Autodesk Fusion 360 part; units mm, degrees
(part 3 of 3)
  line L378 (13, -21.2) -> (9, -21.2)
  line L379 (9, -21.2) -> (9, -21.8)
  line L380 (10.7, -23.5) -> (11.3, -23.5)
  line L381 (11.3, -23.5) -> (11.3, -19.5)
  line L382 (11.3, -19.5) -> (10.7, -19.5)
  line L383 (10.7, -19.5) -> (10.7, -23.5)
  line L384 (-13, -11.3) -> (-9, -11.3)
  line L385 (-9, -11.3) -> (-9, -10.7)
  line L386 (-9, -10.7) -> (-13, -10.7)
  line L387 (-13, -10.7) -> (-13, -11.3)
  line L388 (-11.3, -13) -> (-10.7, -13)
  line L389 (-10.7, -13) -> (-10.7, -9)
  line L390 (-10.7, -9) -> (-11.3, -9)
  line L391 (-11.3, -9) -> (-11.3, -13)
  line L392 (-13, 10.7) -> (-9, 10.7)
  line L393 (-9, 10.7) -> (-9, 11.3)
  line L394 (-9, 11.3) -> (-13, 11.3)
  line L395 (-13, 11.3) -> (-13, 10.7)
  line L396 (-11.3, 9) -> (-10.7, 9)
  line L397 (-10.7, 9) -> (-10.7, 13)
  line L398 (-10.7, 13) -> (-11.3, 13)
  line L399 (-11.3, 13) -> (-11.3, 9)
  line L400 (9, -11.3) -> (13, -11.3)
  line L401 (13, -11.3) -> (13, -10.7)
  line L402 (13, -10.7) -> (9, -10.7)
  line L403 (9, -10.7) -> (9, -11.3)
  line L404 (10.7, -13) -> (11.3, -13)
  line L405 (11.3, -13) -> (11.3, -9)
  line L406 (11.3, -9) -> (10.7, -9)
  line L407 (10.7, -9) -> (10.7, -13)
  line L408 (9, 10.7) -> (13, 10.7)
  line L409 (13, 10.7) -> (13, 11.3)
  line L410 (13, 11.3) -> (9, 11.3)
  line L411 (9, 11.3) -> (9, 10.7)
  line L412 (10.7, 9) -> (11.3, 9)
  line L413 (11.3, 9) -> (11.3, 13)
  line L414 (11.3, 13) -> (10.7, 13)
  line L415 (10.7, 13) -> (10.7, 9)
  line L416 (-13, 21.2) -> (-9, 21.2)
  line L417 (-9, 21.2) -> (-9, 21.8)
  line L418 (-9, 21.8) -> (-13, 21.8)
  line L419 (-13, 21.8) -> (-13, 21.2)
  line L420 (-11.3, 19.5) -> (-10.7, 19.5)
  line L421 (-10.7, 19.5) -> (-10.7, 23.5)
  line L422 (-10.7, 23.5) -> (-11.3, 23.5)
  line L423 (-11.3, 23.5) -> (-11.3, 19.5)
  line L424 (-13, 43.2) -> (-9, 43.2)
  line L425 (-9, 43.2) -> (-9, 43.8)
  line L426 (-9, 43.8) -> (-13, 43.8)
  line L427 (-13, 43.8) -> (-13, 43.2)
  line L428 (-11.3, 41.5) -> (-10.7, 41.5)
  line L429 (-10.7, 41.5) -> (-10.7, 45.5)
  line L430 (-10.7, 45.5) -> (-11.3, 45.5)
  line L431 (-11.3, 45.5) -> (-11.3, 41.5)
  line L432 (9, 21.2) -> (13, 21.2)
  line L433 (13, 21.2) -> (13, 21.8)
  line L434 (13, 21.8) -> (9, 21.8)
  line L435 (9, 21.8) -> (9, 21.2)
  line L436 (10.7, 19.5) -> (11.3, 19.5)
  line L437 (11.3, 19.5) -> (11.3, 23.5)
  line L438 (11.3, 23.5) -> (10.7, 23.5)
  line L439 (10.7, 23.5) -> (10.7, 19.5)
  line L440 (9, 43.2) -> (13, 43.2)
  line L441 (13, 43.2) -> (13, 43.8)
  line L442 (13, 43.8) -> (9, 43.8)
  line L443 (9, 43.8) -> (9, 43.2)
  line L444 (10.7, 41.5) -> (11.3, 41.5)
  line L445 (11.3, 41.5) -> (11.3, 45.5)
  line L446 (11.3, 45.5) -> (10.7, 45.5)
  line L447 (10.7, 45.5) -> (10.7, 41.5)
  line L448 (-13, 53.7) -> (-9, 53.7)
  line L449 (-9, 53.7) -> (-9, 54.3)
  line L450 (-9, 54.3) -> (-13, 54.3)
  line L451 (-13, 54.3) -> (-13, 53.7)
  line L452 (-11.3, 52) -> (-10.7, 52)
  line L453 (-10.7, 52) -> (-10.7, 56)
  line L454 (-10.7, 56) -> (-11.3, 56)
  line L455 (-11.3, 56) -> (-11.3, 52)
  line L456 (-13, 75.7) -> (-9, 75.7)
  line L457 (-9, 75.7) -> (-9, 76.3)
  line L458 (-9, 76.3) -> (-13, 76.3)
  line L459 (-13, 76.3) -> (-13, 75.7)
  line L460 (-11.3, 74) -> (-10.7, 74)
  line L461 (-10.7, 74) -> (-10.7, 78)
  line L462 (-10.7, 78) -> (-11.3, 78)
  line L463 (-11.3, 78) -> (-11.3, 74)
  line L464 (9, 53.7) -> (13, 53.7)
  line L465 (13, 53.7) -> (13, 54.3)
  line L466 (13, 54.3) -> (9, 54.3)
  line L467 (9, 54.3) -> (9, 53.7)
  line L468 (10.7, 52) -> (11.3, 52)
  line L469 (11.3, 52) -> (11.3, 56)
  line L470 (11.3, 56) -> (10.7, 56)
  line L471 (10.7, 56) -> (10.7, 52)
  line L472 (9, 75.7) -> (13, 75.7)
  line L473 (13, 75.7) -> (13, 76.3)
  line L474 (13, 76.3) -> (9, 76.3)
  line L475 (9, 76.3) -> (9, 75.7)
  line L476 (10.7, 74) -> (11.3, 74)
  line L477 (11.3, 74) -> (11.3, 78)
  line L478 (11.3, 78) -> (10.7, 78)
  line L479 (10.7, 78) -> (10.7, 74)
  line L480 (19.5, -76.3) -> (23.5, -76.3)
  line L481 (23.5, -76.3) -> (23.5, -75.7)
  line L482 (23.5, -75.7) -> (19.5, -75.7)
  line L483 (19.5, -75.7) -> (19.5, -76.3)
  line L484 (21.2, -78) -> (21.8, -78)
  line L485 (21.8, -78) -> (21.8, -74)
  line L486 (21.8, -74) -> (21.2, -74)
  line L487 (21.2, -74) -> (21.2, -78)
  line L488 (19.5, -54.3) -> (23.5, -54.3)
  line L489 (23.5, -54.3) -> (23.5, -53.7)
  line L490 (23.5, -53.7) -> (19.5, -53.7)
  line L491 (19.5, -53.7) -> (19.5, -54.3)
  line L492 (21.2, -56) -> (21.8, -56)
  line L493 (21.8, -56) -> (21.8, -52)
  line L494 (21.8, -52) -> (21.2, -52)
  line L495 (21.2, -52) -> (21.2, -56)
  line L496 (41.5, -76.3) -> (45.5, -76.3)
  line L497 (45.5, -76.3) -> (45.5, -75.7)
  line L498 (45.5, -75.7) -> (41.5, -75.7)
  line L499 (41.5, -75.7) -> (41.5, -76.3)
  line L500 (43.2, -78) -> (43.8, -78)
  line L501 (43.8, -78) -> (43.8, -74)
  line L502 (43.8, -74) -> (43.2, -74)
  line L503 (43.2, -74) -> (43.2, -78)
  line L504 (41.5, -54.3) -> (45.5, -54.3)
  line L505 (45.5, -54.3) -> (45.5, -53.7)
  line L506 (45.5, -53.7) -> (41.5, -53.7)
  line L507 (41.5, -53.7) -> (41.5, -54.3)
  line L508 (43.2, -56) -> (43.8, -56)
  line L509 (43.8, -56) -> (43.8, -52)
  line L510 (43.8, -52) -> (43.2, -52)
  line L511 (43.2, -52) -> (43.2, -56)
  line L512 (19.5, -43.8) -> (23.5, -43.8)
  line L513 (23.5, -43.8) -> (23.5, -43.2)
  line L514 (23.5, -43.2) -> (19.5, -43.2)
  line L515 (19.5, -43.2) -> (19.5, -43.8)
  line L516 (21.2, -45.5) -> (21.8, -45.5)
  line L517 (21.8, -45.5) -> (21.8, -41.5)
  line L518 (21.8, -41.5) -> (21.2, -41.5)
  line L519 (21.2, -41.5) -> (21.2, -45.5)
  line L520 (19.5, -21.8) -> (23.5, -21.8)
  line L521 (23.5, -21.8) -> (23.5, -21.2)
  line L522 (23.5, -21.2) -> (19.5, -21.2)
  line L523 (19.5, -21.2) -> (19.5, -21.8)
  line L524 (21.2, -23.5) -> (21.8, -23.5)
  line L525 (21.8, -23.5) -> (21.8, -19.5)
  line L526 (21.8, -19.5) -> (21.2, -19.5)
  line L527 (21.2, -19.5) -> (21.2, -23.5)
  line L528 (41.5, -43.8) -> (45.5, -43.8)
  line L529 (45.5, -43.8) -> (45.5, -43.2)
  line L530 (45.5, -43.2) -> (41.5, -43.2)
  line L531 (41.5, -43.2) -> (41.5, -43.8)
  line L532 (43.2, -45.5) -> (43.8, -45.5)
  line L533 (43.8, -45.5) -> (43.8, -41.5)
  line L534 (43.8, -41.5) -> (43.2, -41.5)
  line L535 (43.2, -41.5) -> (43.2, -45.5)
  line L536 (41.5, -21.8) -> (45.5, -21.8)
  line L537 (45.5, -21.8) -> (45.5, -21.2)
  line L538 (45.5, -21.2) -> (41.5, -21.2)
  line L539 (41.5, -21.2) -> (41.5, -21.8)
  line L540 (43.2, -23.5) -> (43.8, -23.5)
  line L541 (43.8, -23.5) -> (43.8, -19.5)
  line L542 (43.8, -19.5) -> (43.2, -19.5)
  line L543 (43.2, -19.5) -> (43.2, -23.5)
  line L544 (19.5, -11.3) -> (23.5, -11.3)
  line L545 (23.5, -11.3) -> (23.5, -10.7)
  line L546 (23.5, -10.7) -> (19.5, -10.7)
  line L547 (19.5, -10.7) -> (19.5, -11.3)
  line L548 (21.2, -13) -> (21.8, -13)
  line L549 (21.8, -13) -> (21.8, -9)
  line L550 (21.8, -9) -> (21.2, -9)
  line L551 (21.2, -9) -> (21.2, -13)
  line L552 (19.5, 10.7) -> (23.5, 10.7)
  line L553 (23.5, 10.7) -> (23.5, 11.3)
  line L554 (23.5, 11.3) -> (19.5, 11.3)
  line L555 (19.5, 11.3) -> (19.5, 10.7)
  line L556 (21.2, 9) -> (21.8, 9)
  line L557 (21.8, 9) -> (21.8, 13)
  line L558 (21.8, 13) -> (21.2, 13)
  line L559 (21.2, 13) -> (21.2, 9)
  line L560 (41.5, -11.3) -> (45.5, -11.3)
  line L561 (45.5, -11.3) -> (45.5, -10.7)
  line L562 (45.5, -10.7) -> (41.5, -10.7)
  line L563 (41.5, -10.7) -> (41.5, -11.3)
  line L564 (43.2, -13) -> (43.8, -13)
  line L565 (43.8, -13) -> (43.8, -9)
  line L566 (43.8, -9) -> (43.2, -9)
  line L567 (43.2, -9) -> (43.2, -13)
  line L568 (41.5, 10.7) -> (45.5, 10.7)
  line L569 (45.5, 10.7) -> (45.5, 11.3)
  line L570 (45.5, 11.3) -> (41.5, 11.3)
  line L571 (41.5, 11.3) -> (41.5, 10.7)
  line L572 (43.2, 9) -> (43.8, 9)
  line L573 (43.8, 9) -> (43.8, 13)
  line L574 (43.8, 13) -> (43.2, 13)
  line L575 (43.2, 13) -> (43.2, 9)
  line L576 (19.5, 21.2) -> (23.5, 21.2)
  line L577 (23.5, 21.2) -> (23.5, 21.8)
  line L578 (23.5, 21.8) -> (19.5, 21.8)
  line L579 (19.5, 21.8) -> (19.5, 21.2)
  line L580 (21.2, 19.5) -> (21.8, 19.5)
  line L581 (21.8, 19.5) -> (21.8, 23.5)
  line L582 (21.8, 23.5) -> (21.2, 23.5)
  line L583 (21.2, 23.5) -> (21.2, 19.5)
  line L584 (19.5, 43.2) -> (23.5, 43.2)
  line L585 (23.5, 43.2) -> (23.5, 43.8)
  line L586 (23.5, 43.8) -> (19.5, 43.8)
  line L587 (19.5, 43.8) -> (19.5, 43.2)
  line L588 (21.2, 41.5) -> (21.8, 41.5)
  line L589 (21.8, 41.5) -> (21.8, 45.5)
  line L590 (21.8, 45.5) -> (21.2, 45.5)
  line L591 (21.2, 45.5) -> (21.2, 41.5)
  line L592 (41.5, 21.2) -> (45.5, 21.2)
  line L593 (45.5, 21.2) -> (45.5, 21.8)
  line L594 (45.5, 21.8) -> (41.5, 21.8)
  line L595 (41.5, 21.8) -> (41.5, 21.2)
  line L596 (43.2, 19.5) -> (43.8, 19.5)
  line L597 (43.8, 19.5) -> (43.8, 23.5)
  line L598 (43.8, 23.5) -> (43.2, 23.5)
  line L599 (43.2, 23.5) -> (43.2, 19.5)
  line L600 (41.5, 43.2) -> (45.5, 43.2)
  line L601 (45.5, 43.2) -> (45.5, 43.8)
  line L602 (45.5, 43.8) -> (41.5, 43.8)
  line L603 (41.5, 43.8) -> (41.5, 43.2)
  line L604 (43.2, 41.5) -> (43.8, 41.5)
  line L605 (43.8, 41.5) -> (43.8, 45.5)
  line L606 (43.8, 45.5) -> (43.2, 45.5)
  line L607 (43.2, 45.5) -> (43.2, 41.5)
  line L608 (19.5, 53.7) -> (23.5, 53.7)
  line L609 (23.5, 53.7) -> (23.5, 54.3)
  line L610 (23.5, 54.3) -> (19.5, 54.3)
  line L611 (19.5, 54.3) -> (19.5, 53.7)
  line L612 (21.2, 52) -> (21.8, 52)
  line L613 (21.8, 52) -> (21.8, 56)
  line L614 (21.8, 56) -> (21.2, 56)
  line L615 (21.2, 56) -> (21.2, 52)
  line L616 (19.5, 75.7) -> (23.5, 75.7)
  line L617 (23.5, 75.7) -> (23.5, 76.3)
  line L618 (23.5, 76.3) -> (19.5, 76.3)
  line L619 (19.5, 76.3) -> (19.5, 75.7)
  line L620 (21.2, 74) -> (21.8, 74)
  line L621 (21.8, 74) -> (21.8, 78)
  line L622 (21.8, 78) -> (21.2, 78)
  line L623 (21.2, 78) -> (21.2, 74)
  line L624 (41.5, 53.7) -> (45.5, 53.7)
  line L625 (45.5, 53.7) -> (45.5, 54.3)
  line L626 (45.5, 54.3) -> (41.5, 54.3)
  line L627 (41.5, 54.3) -> (41.5, 53.7)
  line L628 (43.2, 52) -> (43.8, 52)
  line L629 (43.8, 52) -> (43.8, 56)
  line L630 (43.8, 56) -> (43.2, 56)
  line L631 (43.2, 56) -> (43.2, 52)
  line L632 (41.5, 75.7) -> (45.5, 75.7)
  line L633 (45.5, 75.7) -> (45.5, 76.3)
  line L634 (45.5, 76.3) -> (41.5, 76.3)
  line L635 (41.5, 76.3) -> (41.5, 75.7)
  line L636 (43.2, 74) -> (43.8, 74)
  line L637 (43.8, 74) -> (43.8, 78)
  line L638 (43.8, 78) -> (43.2, 78)
  line L639 (43.2, 78) -> (43.2, 74)
  line L640 (52, -76.3) -> (56, -76.3)
  line L641 (56, -76.3) -> (56, -75.7)
  line L642 (56, -75.7) -> (52, -75.7)
  line L643 (52, -75.7) -> (52, -76.3)
  line L644 (53.7, -78) -> (54.3, -78)
  line L645 (54.3, -78) -> (54.3, -74)
  line L646 (54.3, -74) -> (53.7, -74)
  line L647 (53.7, -74) -> (53.7, -78)
  line L648 (52, -54.3) -> (56, -54.3)
  line L649 (56, -54.3) -> (56, -53.7)
  line L650 (56, -53.7) -> (52, -53.7)
  line L651 (52, -53.7) -> (52, -54.3)
  line L652 (53.7, -56) -> (54.3, -56)
  line L653 (54.3, -56) -> (54.3, -52)
  line L654 (54.3, -52) -> (53.7, -52)
  line L655 (53.7, -52) -> (53.7, -56)
  line L656 (74, -76.3) -> (78, -76.3)
  line L657 (78, -76.3) -> (78, -75.7)
  line L658 (78, -75.7) -> (74, -75.7)
  line L659 (74, -75.7) -> (74, -76.3)
  line L660 (75.7, -78) -> (76.3, -78)
  line L661 (76.3, -78) -> (76.3, -74)
  line L662 (76.3, -74) -> (75.7, -74)
  line L663 (75.7, -74) -> (75.7, -78)
  line L664 (74, -54.3) -> (78, -54.3)
  line L665 (78, -54.3) -> (78, -53.7)
  line L666 (78, -53.7) -> (74, -53.7)
  line L667 (74, -53.7) -> (74, -54.3)
  line L668 (75.7, -56) -> (76.3, -56)
  line L669 (76.3, -56) -> (76.3, -52)
  line L670 (76.3, -52) -> (75.7, -52)
  line L671 (75.7, -52) -> (75.7, -56)
  line L672 (52, -43.8) -> (56, -43.8)
  line L673 (56, -43.8) -> (56, -43.2)
  line L674 (56, -43.2) -> (52, -43.2)
  line L675 (52, -43.2) -> (52, -43.8)
  line L676 (53.7, -45.5) -> (54.3, -45.5)
  line L677 (54.3, -45.5) -> (54.3, -41.5)
  line L678 (54.3, -41.5) -> (53.7, -41.5)
  line L679 (53.7, -41.5) -> (53.7, -45.5)
  line L680 (52, -21.8) -> (56, -21.8)
  line L681 (56, -21.8) -> (56, -21.2)
  line L682 (56, -21.2) -> (52, -21.2)
  line L683 (52, -21.2) -> (52, -21.8)
  line L684 (53.7, -23.5) -> (54.3, -23.5)
  line L685 (54.3, -23.5) -> (54.3, -19.5)
  line L686 (54.3, -19.5) -> (53.7, -19.5)
  line L687 (53.7, -19.5) -> (53.7, -23.5)
  line L688 (74, -43.8) -> (78, -43.8)
  line L689 (78, -43.8) -> (78, -43.2)
  line L690 (78, -43.2) -> (74, -43.2)
  line L691 (74, -43.2) -> (74, -43.8)
  line L692 (75.7, -45.5) -> (76.3, -45.5)
  line L693 (76.3, -45.5) -> (76.3, -41.5)
  line L694 (76.3, -41.5) -> (75.7, -41.5)
  line L695 (75.7, -41.5) -> (75.7, -45.5)
  line L696 (74, -21.8) -> (78, -21.8)
  line L697 (78, -21.8) -> (78, -21.2)
  line L698 (78, -21.2) -> (74, -21.2)
  line L699 (74, -21.2) -> (74, -21.8)
  line L700 (75.7, -23.5) -> (76.3, -23.5)
  line L701 (76.3, -23.5) -> (76.3, -19.5)
  line L702 (76.3, -19.5) -> (75.7, -19.5)
  line L703 (75.7, -19.5) -> (75.7, -23.5)
  line L704 (52, -11.3) -> (56, -11.3)
  line L705 (56, -11.3) -> (56, -10.7)
  line L706 (56, -10.7) -> (52, -10.7)
  line L707 (52, -10.7) -> (52, -11.3)
  line L708 (53.7, -13) -> (54.3, -13)
  line L709 (54.3, -13) -> (54.3, -9)
  line L710 (54.3, -9) -> (53.7, -9)
  line L711 (53.7, -9) -> (53.7, -13)
  line L712 (52, 10.7) -> (56, 10.7)
  line L713 (56, 10.7) -> (56, 11.3)
  line L714 (56, 11.3) -> (52, 11.3)
  line L715 (52, 11.3) -> (52, 10.7)
  line L716 (53.7, 9) -> (54.3, 9)
  line L717 (54.3, 9) -> (54.3, 13)
  line L718 (54.3, 13) -> (53.7, 13)
  line L719 (53.7, 13) -> (53.7, 9)
  line L720 (74, -11.3) -> (78, -11.3)
  line L721 (78, -11.3) -> (78, -10.7)
  line L722 (78, -10.7) -> (74, -10.7)
  line L723 (74, -10.7) -> (74, -11.3)
  line L724 (75.7, -13) -> (76.3, -13)
  line L725 (76.3, -13) -> (76.3, -9)
  line L726 (76.3, -9) -> (75.7, -9)
  line L727 (75.7, -9) -> (75.7, -13)
  line L728 (74, 10.7) -> (78, 10.7)
  line L729 (78, 10.7) -> (78, 11.3)
  line L730 (78, 11.3) -> (74, 11.3)
  line L731 (74, 11.3) -> (74, 10.7)
  line L732 (75.7, 9) -> (76.3, 9)
  line L733 (76.3, 9) -> (76.3, 13)
  line L734 (76.3, 13) -> (75.7, 13)
  line L735 (75.7, 13) -> (75.7, 9)
  line L736 (52, 21.2) -> (56, 21.2)
  line L737 (56, 21.2) -> (56, 21.8)
  line L738 (56, 21.8) -> (52, 21.8)
  line L739 (52, 21.8) -> (52, 21.2)
  line L740 (53.7, 19.5) -> (54.3, 19.5)
  line L741 (54.3, 19.5) -> (54.3, 23.5)
  line L742 (54.3, 23.5) -> (53.7, 23.5)
  line L743 (53.7, 23.5) -> (53.7, 19.5)
  line L744 (52, 43.2) -> (56, 43.2)
  line L745 (56, 43.2) -> (56, 43.8)
  line L746 (56, 43.8) -> (52, 43.8)
  line L747 (52, 43.8) -> (52, 43.2)
  line L748 (53.7, 41.5) -> (54.3, 41.5)
  line L749 (54.3, 41.5) -> (54.3, 45.5)
  line L750 (54.3, 45.5) -> (53.7, 45.5)
  line L751 (53.7, 45.5) -> (53.7, 41.5)
  line L752 (74, 21.2) -> (78, 21.2)
  line L753 (78, 21.2) -> (78, 21.8)
  line L754 (78, 21.8) -> (74, 21.8)
  line L755 (74, 21.8) -> (74, 21.2)
  line L756 (75.7, 19.5) -> (76.3, 19.5)
  line L757 (76.3, 19.5) -> (76.3, 23.5)
  line L758 (76.3, 23.5) -> (75.7, 23.5)
  line L759 (75.7, 23.5) -> (75.7, 19.5)
  line L760 (74, 43.2) -> (78, 43.2)
  line L761 (78, 43.2) -> (78, 43.8)
  line L762 (78, 43.8) -> (74, 43.8)
  line L763 (74, 43.8) -> (74, 43.2)
  line L764 (75.7, 41.5) -> (76.3, 41.5)
  line L765 (76.3, 41.5) -> (76.3, 45.5)
  line L766 (76.3, 45.5) -> (75.7, 45.5)
  line L767 (75.7, 45.5) -> (75.7, 41.5)
  line L768 (52, 53.7) -> (56, 53.7)
  line L769 (56, 53.7) -> (56, 54.3)
  line L770 (56, 54.3) -> (52, 54.3)
  line L771 (52, 54.3) -> (52, 53.7)
  line L772 (53.7, 52) -> (54.3, 52)
  line L773 (54.3, 52) -> (54.3, 56)
  line L774 (54.3, 56) -> (53.7, 56)
  line L775 (53.7, 56) -> (53.7, 52)
  line L776 (52, 75.7) -> (56, 75.7)
  line L777 (56, 75.7) -> (56, 76.3)
  line L778 (56, 76.3) -> (52, 76.3)
  line L779 (52, 76.3) -> (52, 75.7)
  line L780 (53.7, 74) -> (54.3, 74)
  line L781 (54.3, 74) -> (54.3, 78)
  line L782 (54.3, 78) -> (53.7, 78)
  line L783 (53.7, 78) -> (53.7, 74)
  line L784 (74, 53.7) -> (78, 53.7)
  line L785 (78, 53.7) -> (78, 54.3)
  line L786 (78, 54.3) -> (74, 54.3)
  line L787 (74, 54.3) -> (74, 53.7)
  line L788 (75.7, 52) -> (76.3, 52)
  line L789 (76.3, 52) -> (76.3, 56)
  line L790 (76.3, 56) -> (75.7, 56)
  line L791 (75.7, 56) -> (75.7, 52)
  line L792 (74, 75.7) -> (78, 75.7)
  line L793 (78, 75.7) -> (78, 76.3)
  line L794 (78, 76.3) -> (74, 76.3)
  line L795 (74, 76.3) -> (74, 75.7)
  line L796 (75.7, 74) -> (76.3, 74)
  line L797 (76.3, 74) -> (76.3, 78)
  line L798 (76.3, 78) -> (75.7, 78)
  line L799 (75.7, 78) -> (75.7, 74)
extrude "scale_crosses (1)" cut sketch "scale_crosses" against normal blind 0.4 bodies 1 in component "drop_plate"
ref_plane "WorkPlane1" through (0, 0, 0) normal (0, 0, 1) x (1, 0, 0) in component "atoms3_mock"
sketch "outer" plane through (0, 0, 0) normal (0, 0, 1) x (1, 0, 0) in component "atoms3_mock"
  line L0 (-9, -12) -> (9, -12)
  line L1 (12, -9) -> (12, 9)
  line L2 (9, 12) -> (-9, 12)
  line L3 (-12, 9) -> (-12, -9)
  arc A0 (9, -12) -> (12, -9) centre (9, -9) ccw
  arc A1 (12, 9) -> (9, 12) centre (9, 9) ccw
  arc A2 (-9, 12) -> (-12, 9) centre (-9, 9) ccw
  arc A3 (-12, -9) -> (-9, -12) centre (-9, -9) ccw
  constraint tangent L0 A0
  constraint tangent L1 A0
  constraint tangent L1 A1
  constraint tangent L2 A1
  constraint tangent L2 A2
  constraint tangent L3 A2
  constraint tangent L3 A3
  constraint tangent L0 A3
extrude "outer (1)" add sketch "outer" along normal blind 12.9 separate body makes body 2 in component "atoms3_mock"
ref_plane "WorkPlane2" through (0, 0, 0) normal (0, 0, 1) x (1, 0, 0) in component "atoms3_mock"
sketch "cavity" plane through (0, 0, 0) normal (0, 0, 1) x (1, 0, 0) in component "atoms3_mock"
  line L0 (-9, -10.4) -> (9, -10.4)
  line L1 (10.4, -9) -> (10.4, 9)
  line L2 (9, 10.4) -> (-9, 10.4)
  line L3 (-10.4, 9) -> (-10.4, -9)
  arc A0 (9, -10.4) -> (10.4, -9) centre (9, -9) ccw
  arc A1 (10.4, 9) -> (9, 10.4) centre (9, 9) ccw
  arc A2 (-9, 10.4) -> (-10.4, 9) centre (-9, 9) ccw
  arc A3 (-10.4, -9) -> (-9, -10.4) centre (-9, -9) ccw
  constraint tangent L0 A0
  constraint tangent L1 A0
  constraint tangent L1 A1
  constraint tangent L2 A1
  constraint tangent L2 A2
  constraint tangent L3 A2
  constraint tangent L3 A3
  constraint tangent L0 A3
extrude "cavity (1)" cut sketch "cavity" along normal blind 9.9 bodies 2 in component "atoms3_mock"
ref_plane "WorkPlane3" through (0, 0, 12.9) normal (0, 0, 1) x (1, 0, 0) in component "atoms3_mock"
sketch "window_chamfer" plane through (0, 0, 12.9) normal (0, 0, 1) x (1, 0, 0) in component "atoms3_mock"
  line L0 (-7.7, -8.9) -> (7.7, -8.9)
  line L1 (8.9, -7.7) -> (8.9, 7.7)
  line L2 (7.7, 8.9) -> (-7.7, 8.9)
  line L3 (-8.9, 7.7) -> (-8.9, -7.7)
  arc A0 (7.7, -8.9) -> (8.9, -7.7) centre (7.7, -7.7) ccw
  arc A1 (8.9, 7.7) -> (7.7, 8.9) centre (7.7, 7.7) ccw
  arc A2 (-7.7, 8.9) -> (-8.9, 7.7) centre (-7.7, 7.7) ccw
  arc A3 (-8.9, -7.7) -> (-7.7, -8.9) centre (-7.7, -7.7) ccw
  constraint tangent L0 A0
  constraint tangent L1 A0
  constraint tangent L1 A1
  constraint tangent L2 A1
  constraint tangent L2 A2
  constraint tangent L3 A2
  constraint tangent L3 A3
  constraint tangent L0 A3
extrude "window_chamfer (1)" cut sketch "window_chamfer" against normal blind 0.8 draft -45 bodies 2 in component "atoms3_mock"
ref_plane "WorkPlane4" through (0, 0, 12.9) normal (0, 0, 1) x (1, 0, 0) in component "atoms3_mock"
sketch "screen_recess" plane through (0, 0, 12.9) normal (0, 0, 1) x (1, 0, 0) in component "atoms3_mock"
  line L0 (-7.7, -8.1) -> (7.7, -8.1)
  line L1 (8.1, -7.7) -> (8.1, 7.7)
  line L2 (7.7, 8.1) -> (-7.7, 8.1)
  line L3 (-8.1, 7.7) -> (-8.1, -7.7)
  arc A0 (7.7, -8.1) -> (8.1, -7.7) centre (7.7, -7.7) ccw
  arc A1 (8.1, 7.7) -> (7.7, 8.1) centre (7.7, 7.7) ccw
  arc A2 (-7.7, 8.1) -> (-8.1, 7.7) centre (-7.7, 7.7) ccw
  arc A3 (-8.1, -7.7) -> (-7.7, -8.1) centre (-7.7, -7.7) ccw
  constraint tangent L0 A0
  constraint tangent L1 A0
  constraint tangent L1 A1
  constraint tangent L2 A1
  constraint tangent L2 A2
  constraint tangent L3 A2
  constraint tangent L3 A3
  constraint tangent L0 A3
extrude "screen_recess (1)" cut sketch "screen_recess" against normal blind 1.2 bodies 2 in component "atoms3_mock"
ref_plane "WorkPlane5" through (0, 0, 11.7) normal (0, 0, 1) x (1, 0, 0) in component "atoms3_mock"
sketch "screen_mark" plane through (0, 0, 11.7) normal (0, 0, 1) x (1, 0, 0) in component "atoms3_mock"
  line L0 (-7, -7.8) -> (7, -7.8)
  line L1 (7.8, -7) -> (7.8, 7)
  line L2 (7, 7.8) -> (-7, 7.8)
  line L3 (-7.8, 7) -> (-7.8, -7)
  arc A0 (7, -7.8) -> (7.8, -7) centre (7, -7) ccw
  arc A1 (7.8, 7) -> (7, 7.8) centre (7, 7) ccw
  arc A2 (-7, 7.8) -> (-7.8, 7) centre (-7, 7) ccw
  arc A3 (-7.8, -7) -> (-7, -7.8) centre (-7, -7) ccw
  line L4 (-6.7, -7.2) -> (6.7, -7.2)
  line L5 (7.2, -6.7) -> (7.2, 6.7)
  line L6 (6.7, 7.2) -> (-6.7, 7.2)
  line L7 (-7.2, 6.7) -> (-7.2, -6.7)
  arc A4 (6.7, -7.2) -> (7.2, -6.7) centre (6.7, -6.7) ccw
  arc A5 (7.2, 6.7) -> (6.7, 7.2) centre (6.7, 6.7) ccw
  arc A6 (-6.7, 7.2) -> (-7.2, 6.7) centre (-6.7, 6.7) ccw
  arc A7 (-7.2, -6.7) -> (-6.7, -7.2) centre (-6.7, -6.7) ccw
  constraint tangent L0 A0
  constraint tangent L1 A0
  constraint tangent L1 A1
  constraint tangent L2 A1
  constraint tangent L2 A2
  constraint tangent L3 A2
  constraint tangent L3 A3
  constraint tangent L0 A3
  constraint tangent L4 A4
  constraint tangent L5 A4
  constraint tangent L5 A5
  constraint tangent L6 A5
  constraint tangent L6 A6
  constraint tangent L7 A6
  constraint tangent L7 A7
  constraint tangent L4 A7
extrude "screen_mark (1)" cut sketch "screen_mark" against normal blind 0.4 bodies 2 in component "atoms3_mock"
ref_plane "WorkPlane6" through (0, 0, 12.9) normal (0, 0, 1) x (1, 0, 0) in component "atoms3_mock"
sketch "frame_ticks" plane through (0, 0, 12.9) normal (0, 0, 1) x (1, 0, 0) in component "atoms3_mock"
  line L0 (-8.3, -10.25) -> (-7.7, -10.25)
  line L1 (-7.7, -10.25) -> (-7.7, -9.25)
  line L2 (-7.7, -9.25) -> (-8.3, -9.25)
  line L3 (-8.3, -9.25) -> (-8.3, -10.25)
  line L4 (-10.25, -8.3) -> (-9.25, -8.3)
  line L5 (-9.25, -8.3) -> (-9.25, -7.7)
  line L6 (-9.25, -7.7) -> (-10.25, -7.7)
  line L7 (-10.25, -7.7) -> (-10.25, -8.3)
  line L8 (-6.3, -10.25) -> (-5.7, -10.25)
  line L9 (-5.7, -10.25) -> (-5.7, -9.25)
  line L10 (-5.7, -9.25) -> (-6.3, -9.25)
  line L11 (-6.3, -9.25) -> (-6.3, -10.25)
  line L12 (-10.25, -6.3) -> (-9.25, -6.3)
  line L13 (-9.25, -6.3) -> (-9.25, -5.7)
  line L14 (-9.25, -5.7) -> (-10.25, -5.7)
  line L15 (-10.25, -5.7) -> (-10.25, -6.3)
  line L16 (-4.3, -10.25) -> (-3.7, -10.25)
  line L17 (-3.7, -10.25) -> (-3.7, -9.25)
  line L18 (-3.7, -9.25) -> (-4.3, -9.25)
  line L19 (-4.3, -9.25) -> (-4.3, -10.25)
  line L20 (-10.25, -4.3) -> (-9.25, -4.3)
  line L21 (-9.25, -4.3) -> (-9.25, -3.7)
  line L22 (-9.25, -3.7) -> (-10.25, -3.7)
  line L23 (-10.25, -3.7) -> (-10.25, -4.3)
  line L24 (-2.3, -10.25) -> (-1.7, -10.25)
  line L25 (-1.7, -10.25) -> (-1.7, -9.25)
  line L26 (-1.7, -9.25) -> (-2.3, -9.25)
  line L27 (-2.3, -9.25) -> (-2.3, -10.25)
  line L28 (-10.25, -2.3) -> (-9.25, -2.3)
  line L29 (-9.25, -2.3) -> (-9.25, -1.7)
  line L30 (-9.25, -1.7) -> (-10.25, -1.7)
  line L31 (-10.25, -1.7) -> (-10.25, -2.3)
  line L32 (-0.3, -10.85) -> (0.3, -10.85)
  line L33 (0.3, -10.85) -> (0.3, -9.25)
  line L34 (0.3, -9.25) -> (-0.3, -9.25)
  line L35 (-0.3, -9.25) -> (-0.3, -10.85)
  line L36 (-10.85, -0.3) -> (-9.25, -0.3)
  line L37 (-9.25, -0.3) -> (-9.25, 0.3)
  line L38 (-9.25, 0.3) -> (-10.85, 0.3)
  line L39 (-10.85, 0.3) -> (-10.85, -0.3)
  line L40 (1.7, -10.25) -> (2.3, -10.25)
  line L41 (2.3, -10.25) -> (2.3, -9.25)
  line L42 (2.3, -9.25) -> (1.7, -9.25)
  line L43 (1.7, -9.25) -> (1.7, -10.25)
  line L44 (-10.25, 1.7) -> (-9.25, 1.7)
  line L45 (-9.25, 1.7) -> (-9.25, 2.3)
  line L46 (-9.25, 2.3) -> (-10.25, 2.3)
  line L47 (-10.25, 2.3) -> (-10.25, 1.7)
  line L48 (3.7, -10.25) -> (4.3, -10.25)
  line L49 (4.3, -10.25) -> (4.3, -9.25)
  line L50 (4.3, -9.25) -> (3.7, -9.25)
  line L51 (3.7, -9.25) -> (3.7, -10.25)
  line L52 (-10.25, 3.7) -> (-9.25, 3.7)
  line L53 (-9.25, 3.7) -> (-9.25, 4.3)
  line L54 (-9.25, 4.3) -> (-10.25, 4.3)
  line L55 (-10.25, 4.3) -> (-10.25, 3.7)
  line L56 (5.7, -10.25) -> (6.3, -10.25)
  line L57 (6.3, -10.25) -> (6.3, -9.25)
  line L58 (6.3, -9.25) -> (5.7, -9.25)
  line L59 (5.7, -9.25) -> (5.7, -10.25)
  line L60 (-10.25, 5.7) -> (-9.25, 5.7)
  line L61 (-9.25, 5.7) -> (-9.25, 6.3)
  line L62 (-9.25, 6.3) -> (-10.25, 6.3)
  line L63 (-10.25, 6.3) -> (-10.25, 5.7)
  line L64 (7.7, -10.25) -> (8.3, -10.25)
  line L65 (8.3, -10.25) -> (8.3, -9.25)
  line L66 (8.3, -9.25) -> (7.7, -9.25)
  line L67 (7.7, -9.25) -> (7.7, -10.25)
  line L68 (-10.25, 7.7) -> (-9.25, 7.7)
  line L69 (-9.25, 7.7) -> (-9.25, 8.3)
  line L70 (-9.25, 8.3) -> (-10.25, 8.3)
  line L71 (-10.25, 8.3) -> (-10.25, 7.7)
extrude "frame_ticks (1)" cut sketch "frame_ticks" against normal blind 0.4 bodies 2 in component "atoms3_mock"
component "drop_plate" placed x (1, 0, 0) y (0, 1, 0) z (0, 0, 1) at (0, 0, 0)
component "atoms3_mock" placed x (1, 0, 0) y (0, 1, 0) z (0, 0, 1) at (0, 0, 0)
equation "gf_fit_adjust = 0 mm" comment "Extra inward offset of the standard Gridfinity foot per side (0 = standard)"
equation "dp_units = 4" comment "Gridfinity units per side"
equation "dp_pitch = 32.5 mm" comment "Drop / cover pitch: 30.6 cover pocket + 1.9 locating post"
equation "dp_plate = 2.5 mm" comment "Plate thickness above the foot top"
equation "dp_cover = 30 mm" comment "Cover glass (polycarbonate 30 x 30 x 1.2, caliper 13.11.26)"
equation "dp_clear = 0.3 mm" comment "Cover clearance per side (Lab 1: 0.4 moved freely, 0.2 jammed)"
equation "dp_gap = 0.6 mm" comment "Spacer pad height = resin layer thickness (3 layers at 0.2); measure each plate"
equation "dp_pad_w = 3 mm" comment "Spacer pad width"
equation "dp_pad_l = 6 mm" comment "Spacer pad length"
equation "dp_pad_c = 13.5 mm" comment "Spacer pad centre from the drop centre (pads under the cover edge midpoints)"
equation "dp_post_h = 2.4 mm" comment "Locating post height above the plate (cover top 1.8)"
equation "dp_mark = 11 mm" comment "Scale crosses at +-this from the drop centre (22 mm apart, under the cover corners)"
equation "dp_mark_len = 4 mm" comment "Scale cross arm length"
equation "groove_w = 0.6 mm" comment "Engraved line width (fill with black marker)"
equation "groove_d = 0.4 mm" comment "Engraved line depth"
equation "at_size = 24 mm" comment "AtomS3 outer size (caliper 13.11.26, M5Stack STL 24.0)"
equation "at_h = 12.9 mm" comment "AtomS3 height (caliper 13.11.26, M5Stack 12.9)"
equation "at_r = 3 mm" comment "AtomS3 plan corner radius (M5Stack STL)"
equation "at_wall = 1.6 mm" comment "Mock wall; open bottom clears the battery pins"
equation "at_roof = 3 mm" comment "Mock roof thickness at the top"
equation "at_win = 17.8 mm" comment "Screen opening at the top face (M5Stack STL)"
equation "at_win_r = 1.2 mm" comment "Screen opening corner radius (M5Stack STL)"
equation "at_win_in = 16.2 mm" comment "Screen opening below the 45 deg chamfer (M5Stack STL)"
equation "at_chamfer = 0.8 mm" comment "45 deg chamfer depth of the opening (M5Stack STL 0.79)"
equation "at_recess = 1.2 mm" comment "Screen surface below the top face (frame thickness in the M5Stack STL; >= real recess)"
equation "at_active = 15 mm" comment "Screen area mark: groove centre line (0.85 in 128 x 128 active area ~15.2)"
equation "at_tick = 2 mm" comment "Scale tick pitch on the frame"
equation "at_count = 6" comment "Number of mock-ups"
equation "d71 = -( 0.80 mm )"
named bodies: "drop_plate", "atoms3_mock"
